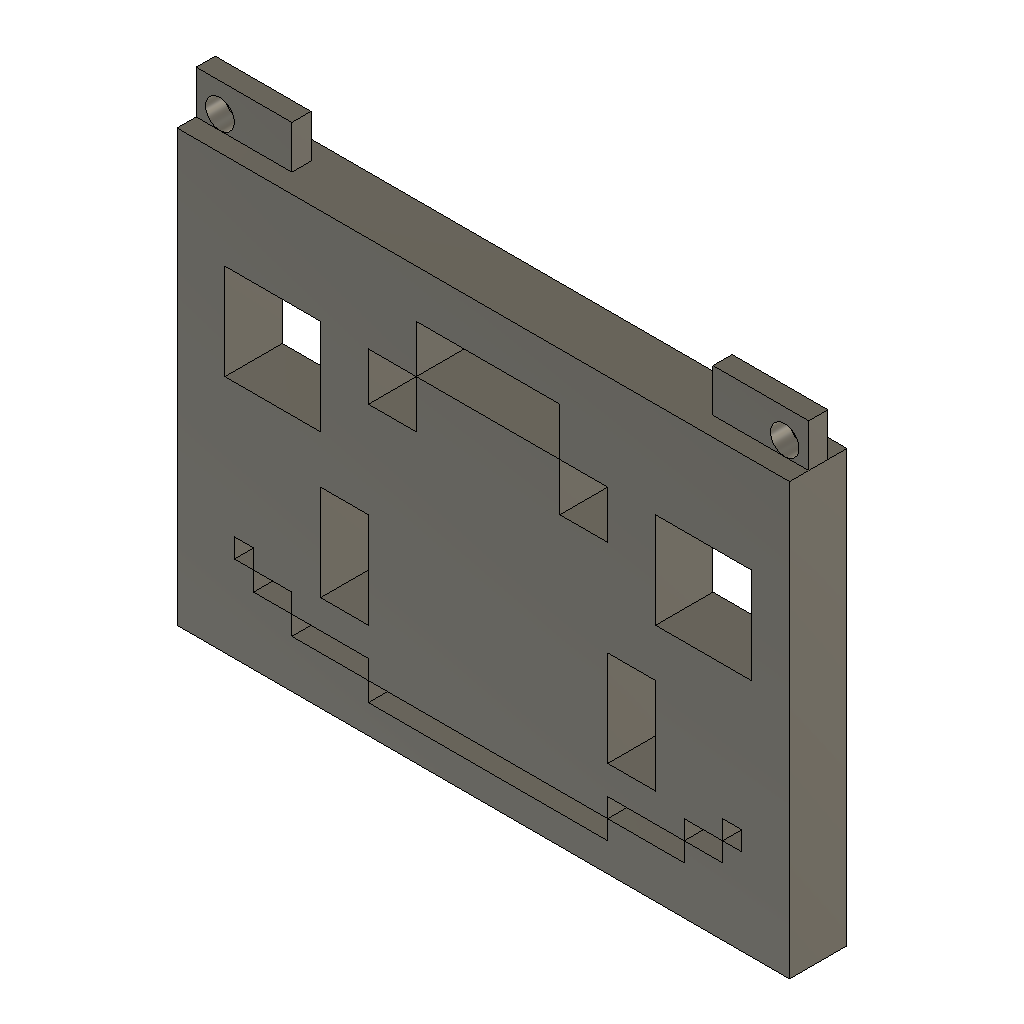
小车设计 (Autodesk Fusion 360 archive; units mm, degrees)
design "挡板1"
part number: 2026-10-10-23-06-53-634
Autodesk Fusion 360 part; units mm, degrees
sketch "草图1" plane through (0, 0, 0) normal (0, 0, 1) x (1, 0, 0)
  line L0 (0, 0) -> (64, 0)
  line L1 (64, 0) -> (64, -6)
  line L2 (64, -6) -> (0, -6)
  line L3 (0, -6) -> (0, 0)
  line L4 (0, -2) -> (10, -2)
  line L5 (0, -4) -> (10, -4)
  line L6 (10, -2) -> (10, -4)
  line L7 (0, -2) -> (0, -4)
  line L8 (64, -2) -> (54, -2)
  line L9 (54, -2) -> (54, -4)
  line L10 (54, -4) -> (64, -4)
  line L11 (64, -2) -> (64, -4)
  dimension "d1" = 64
  dimension "d2" = 6
  constraint horizontal L0
  constraint vertical L1
  constraint horizontal L2
  constraint vertical L3
  constraint coincident L0.start L3.end
  constraint coincident L3 L4.start
  constraint perpendicular L3 L4
  constraint coincident L3 L5.start
  constraint perpendicular L3 L5
  constraint perpendicular L5 L6
  constraint coincident L1 L8.start
  constraint perpendicular L1 L8
  constraint perpendicular L8 L9
  constraint coincident L1 L10.end
  constraint perpendicular L1 L10
  measures "d1" distance of L0.start L0.end
  measures "d2" distance of L0.start L2.end
extrude "拉伸1" add sketch "草图1" along normal blind 4.5 contours L3 L4 L5 L6 L7 | L1 L8 L9 L10 L11 makes body 1 at (3.3333, -2, 1.5) makes body 2 at (60.6667, -2, 1.5)
sketch "草图2" plane through (0, 0, 0) normal (0, 0, 1) x (1, 0, 0)
  line L0 (0, 0) -> (64, 0)
  line L1 (64, 0) -> (64, -6)
  line L2 (64, -6) -> (0, -6)
  line L3 (0, -6) -> (0, 0)
  constraint horizontal L0
  constraint vertical L1
  constraint horizontal L2
  constraint vertical L3
  constraint coincident L0.start L3.end
extrude "拉伸2" add sketch "草图2" against normal blind 45 bodies 1 2
sketch "草图3" plane through (0, 0, 0) normal (0, 1, 0) x (1, 0, 0)
sketch "草图6" plane through (0, -4, 0) normal (0, -1, 0) x (1, 0, 0)
  line L0 (54, 0) -> (64, 0)
  line L1 (64, 0) -> (64, 4.5)
  line L2 (64, 4.5) -> (54, 4.5)
  line L3 (54, 4.5) -> (54, 0)
  line L4 (10, 4.5) -> (0, 4.5)
  line L5 (0, 0) -> (10, 0)
  line L6 (0.9797, 4.5) -> (0.9797, 0)
  circle A0 centre (2.4797, 1.5) radius 1.5
  line L7 (63, 0) -> (63, 4.5)
  circle A1 centre (61.5, 1.5) radius 1.5
  dimension "d15" = 1.5
  dimension "d16" = 1.5
  constraint coincident L4 L6.start
  constraint coincident L5 L6.end
  constraint perpendicular L5 L6
  constraint tangent L6 A0
  constraint tangent L5 A0
  constraint coincident L0 L7.start
  constraint coincident L2 L7.end
  constraint perpendicular L2 L7
  constraint tangent L7 A1
  constraint tangent L0 A1
  measures "d15" radius of A0
  measures "d16" radius of A1
extrude "拉伸5" cut sketch "草图6" against normal blind 9 contours A1 | A0 bodies 1
sketch "草图7" plane through (0, -6, 0) normal (0, -1, 0) x (1, 0, 0)
  line L0 (64, 0) -> (0, 0)
  line L1 (0, 0) -> (0, -45)
  line L2 (0, -45) -> (64, -45)
  line L3 (64, -45) -> (64, 0)
  line L4 (50, -35) -> (45, -35)
  line L5 (45, -35) -> (45, -25)
  line L6 (45, -25) -> (50, -25)
  line L7 (50, -25) -> (50, -35)
  line L8 (20, -35) -> (15, -35)
  line L9 (15, -35) -> (15, -25)
  line L10 (15, -25) -> (20, -25)
  line L11 (20, -25) -> (20, -35)
  line L12 (40, -10) -> (25, -10)
  line L13 (25, -10) -> (25, -5)
  line L14 (25, -5) -> (40, -5)
  line L15 (40, -5) -> (40, -10)
  line L16 (20, -10) -> (25, -10)
  line L17 (25, -10) -> (25, -15)
  line L18 (25, -15) -> (20, -15)
  line L19 (20, -15) -> (20, -10)
  line L20 (45, -10) -> (40, -10)
  line L21 (40, -10) -> (40, -15)
  line L22 (40, -15) -> (45, -15)
  line L23 (45, -15) -> (45, -10)
  line L24 (5, -20) -> (15, -20)
  line L25 (15, -20) -> (15, -10)
  line L26 (15, -10) -> (5, -10)
  line L27 (5, -10) -> (5, -20)
  line L28 (60, -20) -> (50, -20)
  line L29 (50, -20) -> (50, -10)
  line L30 (50, -10) -> (60, -10)
  line L31 (60, -10) -> (60, -20)
  point P0 (45, -25)
  point P1 (50, -25)
  point P2 (50, -35)
  point P3 (45, -35)
  point P4 (20, -35)
  point P5 (15, -35)
  point P6 (15, -25)
  point P7 (20, -25)
  point P8 (40, -10)
  point P9 (25, -10)
  point P10 (40, -5)
  point P11 (25, -5)
  point P12 (45, -10)
  point P13 (20, -10)
  point P14 (60, -20)
  point P15 (5, -20)
  constraint horizontal L4
  constraint vertical L5
  constraint horizontal L6
  constraint vertical L7
  constraint coincident P0 L5.end
  constraint coincident P2 L4.start
  constraint horizontal L8
  constraint vertical L9
  constraint horizontal L10
  constraint vertical L11
  constraint coincident P6 L9.end
  constraint coincident P4 L8.start
  constraint horizontal L12
  constraint vertical L13
  constraint horizontal L14
  constraint vertical L15
  constraint coincident P11 L13.end
  constraint coincident P8 L12.start
  constraint horizontal L16
  constraint vertical L17
  constraint horizontal L18
  constraint vertical L19
  constraint coincident P13 L16.start
  constraint horizontal L20
  constraint vertical L21
  constraint horizontal L22
  constraint vertical L23
  constraint coincident P12 L20.start
  constraint horizontal L24
  constraint vertical L25
  constraint horizontal L26
  constraint vertical L27
  constraint coincident P15 L24.start
  constraint horizontal L28
  constraint vertical L29
  constraint horizontal L30
  constraint vertical L31
  constraint coincident P14 L28.start
extrude "拉伸6" cut sketch "草图7" against normal blind 21 contours L4 L5 L6 L7 | L8 L9 L10 L11 | L16 L17 L18 L19 | L12 L13 L14 L15 | L20 L21 L22 L23 bodies 1
sketch "草图8" plane through (0, 0, 0) normal (0, 1, 0) x (-1, 0, 0)
  line L0 (-45, -25) -> (-45, -35)
  line L1 (-45, -35) -> (-50, -35)
  line L2 (-50, -35) -> (-50, -25)
  line L3 (-50, -25) -> (-45, -25)
  line L4 (-15, -25) -> (-15, -35)
  line L5 (-15, -35) -> (-20, -35)
  line L6 (-20, -35) -> (-20, -25)
  line L7 (-20, -25) -> (-15, -25)
  line L8 (-25, -15) -> (-25, -10)
  line L9 (-25, -10) -> (-40, -10)
  line L10 (-40, -10) -> (-40, -15)
  line L11 (-40, -15) -> (-45, -15)
  line L12 (-45, -15) -> (-45, -10)
  line L13 (-45, -10) -> (-40, -10)
  line L14 (-40, -10) -> (-40, -5)
  line L15 (-40, -5) -> (-25, -5)
  line L16 (-25, -5) -> (-25, -10)
  line L17 (-25, -10) -> (-20, -10)
  line L18 (-20, -10) -> (-20, -15)
  line L19 (-20, -15) -> (-25, -15)
  line L20 (0, 0) -> (-64, 0)
  line L21 (-64, 0) -> (-64, -45)
  line L22 (-64, -45) -> (0, -45)
  line L23 (0, -45) -> (0, 0)
  line L24 (-15, -10) -> (-5, -10)
  line L25 (-5, -10) -> (-5, -20)
  line L26 (-5, -20) -> (-15, -20)
  line L27 (-15, -20) -> (-15, -10)
  line L28 (-50, -10) -> (-60, -10)
  line L29 (-60, -10) -> (-60, -20)
  line L30 (-60, -20) -> (-50, -20)
  line L31 (-50, -20) -> (-50, -10)
  constraint horizontal L24
  constraint vertical L25
  constraint horizontal L26
  constraint vertical L27
  constraint horizontal L28
  constraint vertical L29
  constraint horizontal L30
  constraint vertical L31
extrude "拉伸7" cut sketch "草图8" against normal blind 17 contours L24 L25 L26 L27 | L28 L29 L30 L31 bodies 1
sketch "草图9" plane through (0, -6, 0) normal (0, -1, 0) x (1, 0, 0)
  line L0 (5, -20) -> (5, -10)
  line L1 (5, -10) -> (15, -10)
  line L2 (15, -10) -> (15, -20)
  line L3 (15, -20) -> (5, -20)
  line L4 (50, -10) -> (60, -10)
  line L5 (60, -10) -> (60, -20)
  line L6 (60, -20) -> (50, -20)
  line L7 (50, -20) -> (50, -10)
  line L8 (45, -35) -> (45, -25)
  line L9 (45, -25) -> (50, -25)
  line L10 (50, -25) -> (50, -35)
  line L11 (50, -35) -> (45, -35)
  line L12 (15, -35) -> (15, -25)
  line L13 (15, -25) -> (20, -25)
  line L14 (20, -25) -> (20, -35)
  line L15 (20, -35) -> (15, -35)
  line L16 (25, -10) -> (25, -15)
  line L17 (25, -15) -> (20, -15)
  line L18 (20, -15) -> (20, -10)
  line L19 (20, -10) -> (25, -10)
  line L20 (25, -10) -> (25, -5)
  line L21 (25, -5) -> (40, -5)
  line L22 (40, -5) -> (40, -10)
  line L23 (40, -10) -> (45, -10)
  line L24 (45, -10) -> (45, -15)
  line L25 (45, -15) -> (40, -15)
  line L26 (40, -15) -> (40, -10)
  line L27 (40, -10) -> (25, -10)
  line L28 (64, 0) -> (0, 0)
  line L29 (0, 0) -> (0, -45)
  line L30 (0, -45) -> (64, -45)
  line L31 (64, -45) -> (64, 0)
  line L32 (45, -42) -> (20, -42)
  line L33 (20, -42) -> (20, -40)
  line L34 (20, -40) -> (45, -40)
  line L35 (45, -40) -> (45, -42)
  line L36 (20, -40) -> (12, -40)
  line L37 (12, -40) -> (12, -38)
  line L38 (12, -38) -> (20, -38)
  line L39 (20, -38) -> (20, -40)
  line L40 (12, -38) -> (8, -38)
  line L41 (8, -38) -> (8, -36)
  line L42 (8, -36) -> (12, -36)
  line L43 (12, -36) -> (12, -38)
  line L44 (8, -36) -> (6, -36)
  line L45 (6, -36) -> (6, -34)
  line L46 (6, -34) -> (8, -34)
  line L47 (8, -34) -> (8, -36)
  line L48 (6, -34) -> (4, -34)
  line L49 (4, -34) -> (4, -32)
  line L50 (4, -32) -> (6, -32)
  line L51 (6, -32) -> (6, -34)
  line L52 (4, -32) -> (2, -32)
  line L53 (2, -32) -> (2, -30)
  line L54 (2, -30) -> (4, -30)
  line L55 (4, -30) -> (4, -32)
  line L56 (45, -40) -> (53, -40)
  line L57 (53, -40) -> (53, -38)
  line L58 (53, -38) -> (45, -38)
  line L59 (45, -38) -> (45, -40)
  line L60 (53, -38) -> (57, -38)
  line L61 (57, -38) -> (57, -36)
  line L62 (57, -36) -> (53, -36)
  line L63 (53, -36) -> (53, -38)
  line L64 (57, -36) -> (59, -36)
  line L65 (59, -36) -> (59, -34)
  line L66 (59, -34) -> (57, -34)
  line L67 (57, -34) -> (57, -36)
  line L68 (59, -34) -> (61, -34)
  line L69 (61, -34) -> (61, -32)
  line L70 (61, -32) -> (59, -32)
  line L71 (59, -32) -> (59, -34)
  line L72 (61, -32) -> (63, -32)
  line L73 (63, -32) -> (63, -30)
  line L74 (63, -30) -> (61, -30)
  line L75 (61, -30) -> (61, -32)
  point P0 (45, -42)
  point P1 (20, -42)
  point P2 (16, -39)
  point P3 (18, -40)
  point P4 (12, -38)
  point P5 (8, -36)
  point P6 (6, -34)
  point P7 (4, -32)
  point P8 (4, -30)
  point P9 (2, -30)
  point P10 (45, -40)
  point P11 (20, -40)
  point P12 (53, -38)
  point P13 (57, -36)
  point P14 (59, -34)
  point P15 (61, -32)
  point P16 (63, -30)
  constraint horizontal L32
  constraint vertical L33
  constraint horizontal L34
  constraint vertical L35
  constraint coincident P11 L33.end
  constraint coincident P0 L32.start
  constraint horizontal L36
  constraint vertical L37
  constraint horizontal L38
  constraint vertical L39
  constraint coincident P4 L37.end
  constraint horizontal L40
  constraint vertical L41
  constraint horizontal L42
  constraint vertical L43
  constraint coincident P5 L41.end
  constraint horizontal L44
  constraint vertical L45
  constraint horizontal L46
  constraint vertical L47
  constraint coincident P6 L45.end
  constraint horizontal L48
  constraint vertical L49
  constraint horizontal L50
  constraint vertical L51
  constraint coincident P7 L49.end
  constraint horizontal L52
  constraint vertical L53
  constraint horizontal L54
  constraint vertical L55
  constraint coincident P9 L53.end
  constraint horizontal L56
  constraint vertical L57
  constraint horizontal L58
  constraint vertical L59
  constraint coincident P12 L57.end
  constraint coincident P10 L34.end
  constraint horizontal L60
  constraint vertical L61
  constraint horizontal L62
  constraint vertical L63
  constraint coincident P13 L61.end
  constraint horizontal L64
  constraint vertical L65
  constraint horizontal L66
  constraint vertical L67
  constraint coincident P14 L65.end
  constraint horizontal L68
  constraint vertical L69
  constraint horizontal L70
  constraint vertical L71
  constraint coincident P15 L69.end
  constraint horizontal L72
  constraint vertical L73
  constraint horizontal L74
  constraint vertical L75
  constraint coincident P16 L73.end
extrude "拉伸8" cut sketch "草图9" against normal blind 36 contours L44 L45 L46 L47 | L40 L41 L42 L43 | L36 L37 L38 L39 | L64 L65 L66 L67 | L60 L61 L62 L63 | L56 L57 L58 L59 | L32 L33 L34 L35 bodies 1

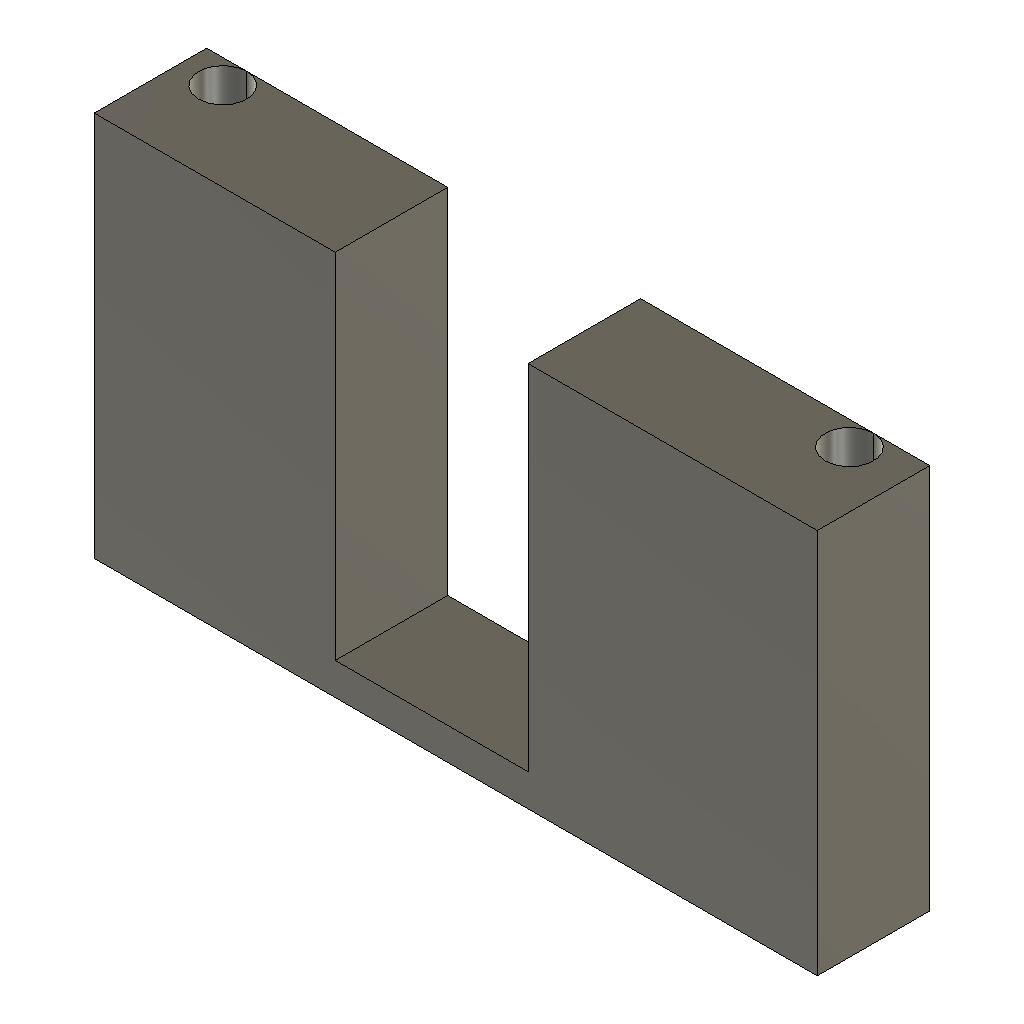
design "舵机固定"
part number: 2026-10-10-18-02-42-564
Autodesk Fusion 360 part; units mm, degrees
sketch "草图3" plane through (0, 0, 0) normal (0, 0, 1) x (1, 0, 0)
  line L0 (0, 0) -> (45, 0)
  line L1 (45, 0) -> (45, -7)
  line L2 (45, -7) -> (0, -7)
  line L3 (0, -7) -> (0, 0)
  point P0 (42, 0)
  point P1 (39, 0)
  point P2 (27, 0)
  point P3 (15, 0)
  point P4 (4.7006, 0)
  point P5 (2, 0)
  dimension "d3" = 45
  constraint horizontal L0
  constraint vertical L1
  constraint horizontal L2
  constraint vertical L3
  constraint coincident L0.start L3.end
  constraint coincident L0 P0
  constraint coincident L0 P1
  constraint coincident L0 P2
  constraint coincident L0 P3
  constraint coincident L0 P4
  constraint coincident L0 P5
  measures "d3" distance of L0.start L0.end
extrude "拉伸1" add sketch "草图3" along normal blind 24
sketch "草图4" plane through (0, 0, 24) normal (0, 0, 1) x (-1, 0, 0)
  line L0 (0, 7) -> (-45, 7)
  line L1 (-45, 7) -> (-45, 0)
  line L2 (-45, 0) -> (0, 0)
  line L3 (0, 0) -> (0, 7)
  line L4 (-15, 0) -> (-27, 0)
  line L5 (-27, 0) -> (-27, 7)
  line L6 (-27, 7) -> (-15, 7)
  line L7 (-15, 7) -> (-15, 0)
  circle A0 centre (-40.5, 1.5) radius 1.5
  circle A1 centre (-2.5001, 1.5001) radius 1.5001
  point P0 (-42, 0)
  point P1 (-39, 0)
  point P2 (-27, 0)
  point P3 (-15, 0)
  point P4 (-4, 0)
  point P5 (-15, 0)
  point P6 (-15, 0)
  dimension "d7" = 3
  constraint coincident L2 P0
  constraint coincident L2 P1
  constraint coincident L2 P2
  constraint coincident L2 P6
  constraint coincident L2 P4
  constraint coincident P6 P5
  constraint horizontal L4
  constraint vertical L5
  constraint horizontal L6
  constraint vertical L7
  constraint coincident L0 L5.end
  measures "d7" diameter of A0
extrude "拉伸2" cut sketch "草图4" against normal blind 22 contours L0 L2 L4 L5 L6 L7
sketch "草图5" plane through (0, 0, 24) normal (0, 0, 1) x (-1, 0, 0)
  line L0 (-15, 7) -> (-15, 0)
  line L1 (-15, 0) -> (0, 0)
  line L2 (0, 0) -> (0, 7)
  line L3 (0, 7) -> (-15, 7)
  line L4 (-1, 0) -> (-4, 0)
  line L5 (-1, 0) -> (-1, 5)
  circle A0 centre (-2.5, 1.5) radius 1.5
  line L6 (-45, 0) -> (-27, 0)
  line L7 (0, 0) -> (-45, 0)
  line L8 (-43, 0) -> (-40, 0)
  line L9 (-40, 4) -> (-40, 0)
  circle A1 centre (-41.5, 1.5) radius 1.5
  dimension "d10" = 1.5
  dimension "d11" = 1.5
  constraint coincident L1 L4.start
  constraint coincident L1 L4.end
  constraint perpendicular L4 L5
  constraint tangent L4 A0
  constraint tangent L5 A0
  constraint coincident L6 L8.start
  constraint coincident L6 L8.end
  constraint perpendicular L6 L9
  constraint tangent L8 A1
  constraint tangent L9 A1
  measures "d10" radius of A0
  measures "d11" radius of A1
extrude "拉伸3" cut sketch "草图5" against normal blind 37 contours A0 | A1

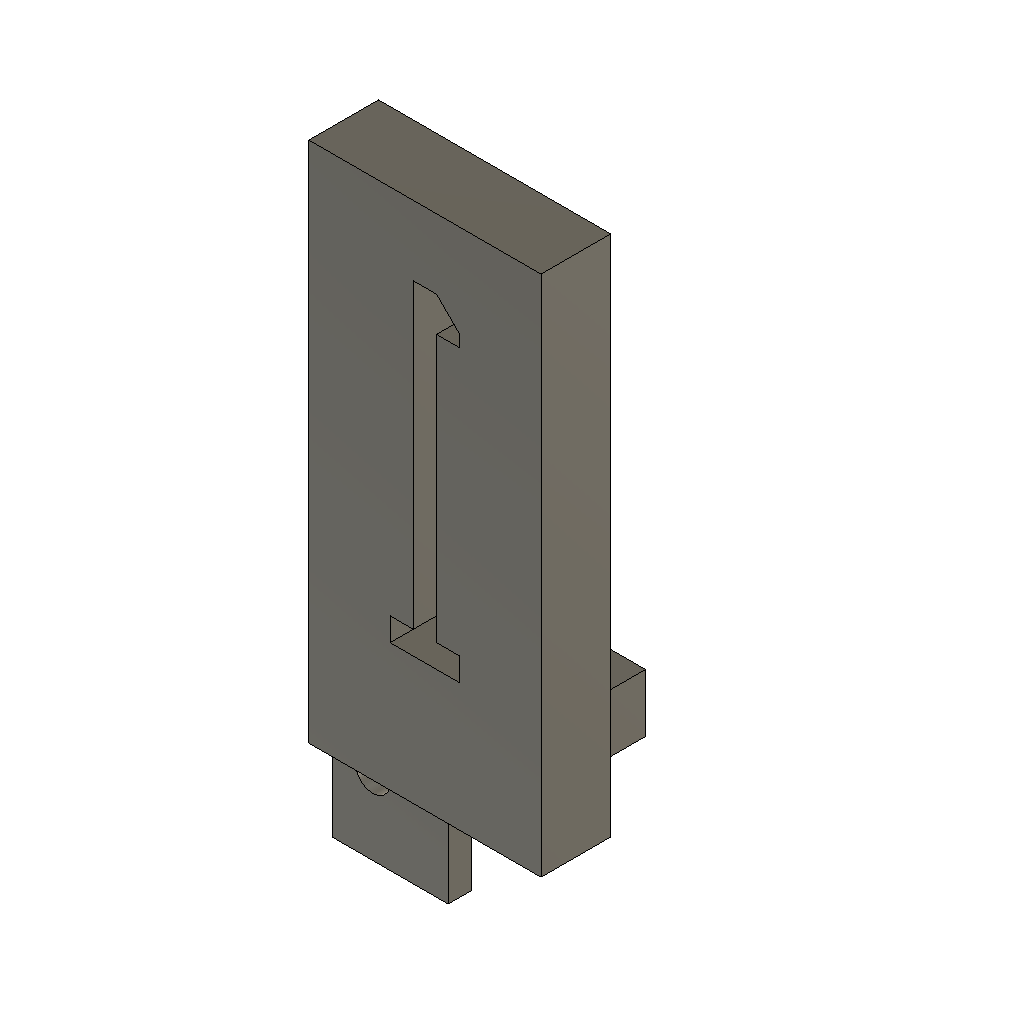
design "挡板2"
part number: 2026-10-11-00-40-43-572
Autodesk Fusion 360 part; units mm, degrees
sketch "草图1" plane through (0, 0, 0) normal (0, 0, 1) x (1, 0, 0)
  line L0 (0, 0) -> (20, 0)
  line L1 (20, 0) -> (20, -6)
  line L2 (20, -6) -> (0, -6)
  line L3 (0, -6) -> (0, 0)
  dimension "d1" = 20
  dimension "d2" = 6
  constraint horizontal L0
  constraint vertical L1
  constraint horizontal L2
  constraint vertical L3
  constraint coincident L0.start L3.end
  measures "d1" distance of L0.start L0.end
  measures "d2" distance of L0.start L2.end
extrude "拉伸1" add sketch "草图1" along normal blind 45
sketch "草图2" plane through (0, 0, 0) normal (0, 0, -1) x (1, 0, 0)
  line L0 (20, 6) -> (0, 6)
  line L1 (0, 6) -> (0, 0)
  line L2 (0, 0) -> (20, 0)
  line L3 (20, 0) -> (20, 6)
  line L4 (0, 4) -> (10, 4)
  line L5 (10, 4) -> (10, 2)
  line L6 (10, 2) -> (0, 2)
  line L7 (0, 4) -> (0, 2)
  constraint coincident L1 L4.start
  constraint perpendicular L1 L4
  constraint perpendicular L4 L5
  constraint coincident L1 L6.end
  constraint perpendicular L1 L6
extrude "拉伸2" add sketch "草图2" along normal blind 8 contours L1 L4 L5 L6 L7
sketch "草图3" plane through (0, -2, 0) normal (0, 1, 0) x (-1, 0, 0)
  line L0 (0, 0) -> (-10, 0)
  line L1 (-10, 0) -> (-10, -8)
  line L2 (-10, -8) -> (0, -8)
  line L3 (0, -8) -> (0, 0)
  line L4 (-2, -8) -> (-2, 0)
  circle A0 centre (-3.5, -1.5) radius 1.5
  dimension "d7" = 1.5
  constraint coincident L2 L4.start
  constraint coincident L0 L4.end
  constraint tangent L4 A0
  constraint tangent L0 A0
  measures "d7" radius of A0
extrude "拉伸3" cut sketch "草图3" against normal blind 20 contours A0
sketch "草图4" plane through (0, 0, 0) normal (0, 1, 0) x (-1, 0, 0)
  line L0 (-20, 0) -> (0, 0)
  line L1 (0, 0) -> (0, 45)
  line L2 (0, 45) -> (-20, 45)
  line L3 (-20, 45) -> (-20, 0)
  line L4 (-8, 0) -> (-8, 5)
  line L5 (-8, 5) -> (-14, 5)
  line L6 (-14, 5) -> (-14, 0)
  constraint coincident L0 L4.start
  constraint perpendicular L0 L4
  constraint perpendicular L4 L5
  constraint coincident L0 L6.end
  constraint perpendicular L0 L6
extrude "拉伸4" add sketch "草图4" along normal blind 9 contours L0 L4 L5 L6
sketch "草图5" plane through (0, 0, 5) normal (0, 0, 1) x (-1, 0, 0)
  line L0 (-8, 0) -> (-14, 0)
  line L1 (-14, 0) -> (-14, -9)
  line L2 (-14, -9) -> (-8, -9)
  line L3 (-8, -9) -> (-8, 0)
  line L4 (-11, 0) -> (-9.5, 0)
  line L5 (-9.5, 0) -> (-9.5, -7)
  line L6 (-9.5, -7) -> (-11, -7)
  line L7 (-11, -7) -> (-11, 0)
  line L8 (-11, 0) -> (-12.5, 0)
  line L9 (-12.5, 0) -> (-12.5, -7)
  line L10 (-12.5, -7) -> (-11, -7)
  line L11 (-11, -7) -> (-11, 0)
  dimension "d12" = 1.5
  dimension "d13" = 7
  dimension "d14" = 7
  constraint horizontal L4
  constraint vertical L5
  constraint horizontal L6
  constraint vertical L7
  constraint midpoint L0 L4.start
  constraint horizontal L8
  constraint vertical L9
  constraint horizontal L10
  constraint vertical L11
  measures "d12" distance of L4.start L4.end
  measures "d13" distance of L4.start L6.end
  measures "d14" distance of L4.start L6.end
extrude "拉伸5" cut sketch "草图5" against normal blind 17 contours L0 L4 L5 L6 L7 L11 | L0 L7 L8 L9 L10 L11
sketch "草图6" plane through (0, 0, 0) normal (0, 1, 0) x (-1, 0, 0)
  line L0 (-8, 5) -> (-8, 0)
  line L1 (-8, 0) -> (0, 0)
  line L2 (0, 0) -> (0, 45)
  line L3 (0, 45) -> (-20, 45)
  line L4 (-20, 45) -> (-20, 0)
  line L5 (-20, 0) -> (-14, 0)
  line L6 (-14, 0) -> (-14, 5)
  line L7 (-14, 5) -> (-12.5, 5)
  line L8 (-12.5, 5) -> (-12.5, 0)
  line L9 (-12.5, 0) -> (-9.5, 0)
  line L10 (-9.5, 0) -> (-9.5, 5)
  line L11 (-9.5, 5) -> (-8, 5)
  line L12 (-11, 13) -> (-9, 13)
  line L13 (-9, 13) -> (-9, 36)
  line L14 (-9, 36) -> (-11, 36)
  line L15 (-11, 36) -> (-11, 13)
  line L16 (-13, 36) -> (-9, 36)
  line L17 (-9, 36) -> (-9, 37)
  line L18 (-9, 37) -> (-13, 37)
  line L19 (-13, 37) -> (-13, 36)
  line L20 (-11, 39) -> (-9, 39)
  line L21 (-9, 39) -> (-9, 37)
  line L22 (-9, 37) -> (-11, 37)
  line L23 (-11, 37) -> (-11, 39)
  line L24 (-11, 39) -> (-13, 37)
  line L25 (-13, 13) -> (-7, 13)
  line L26 (-7, 13) -> (-7, 11)
  line L27 (-7, 11) -> (-13, 11)
  line L28 (-13, 11) -> (-13, 13)
  constraint horizontal L12
  constraint vertical L13
  constraint horizontal L14
  constraint vertical L15
  constraint horizontal L16
  constraint vertical L17
  constraint horizontal L18
  constraint vertical L19
  constraint horizontal L20
  constraint vertical L21
  constraint horizontal L22
  constraint vertical L23
  constraint horizontal L25
  constraint vertical L26
  constraint horizontal L27
  constraint vertical L28
extrude "拉伸6" cut sketch "草图6" against normal blind 10 contours L12 L13 L14 L15 L16 L25 | L12 L25 L26 L27 L28 | L14 L16 L17 L18 L19 L22 | L18 L20 L21 L22 L23 | L18 L23 L24

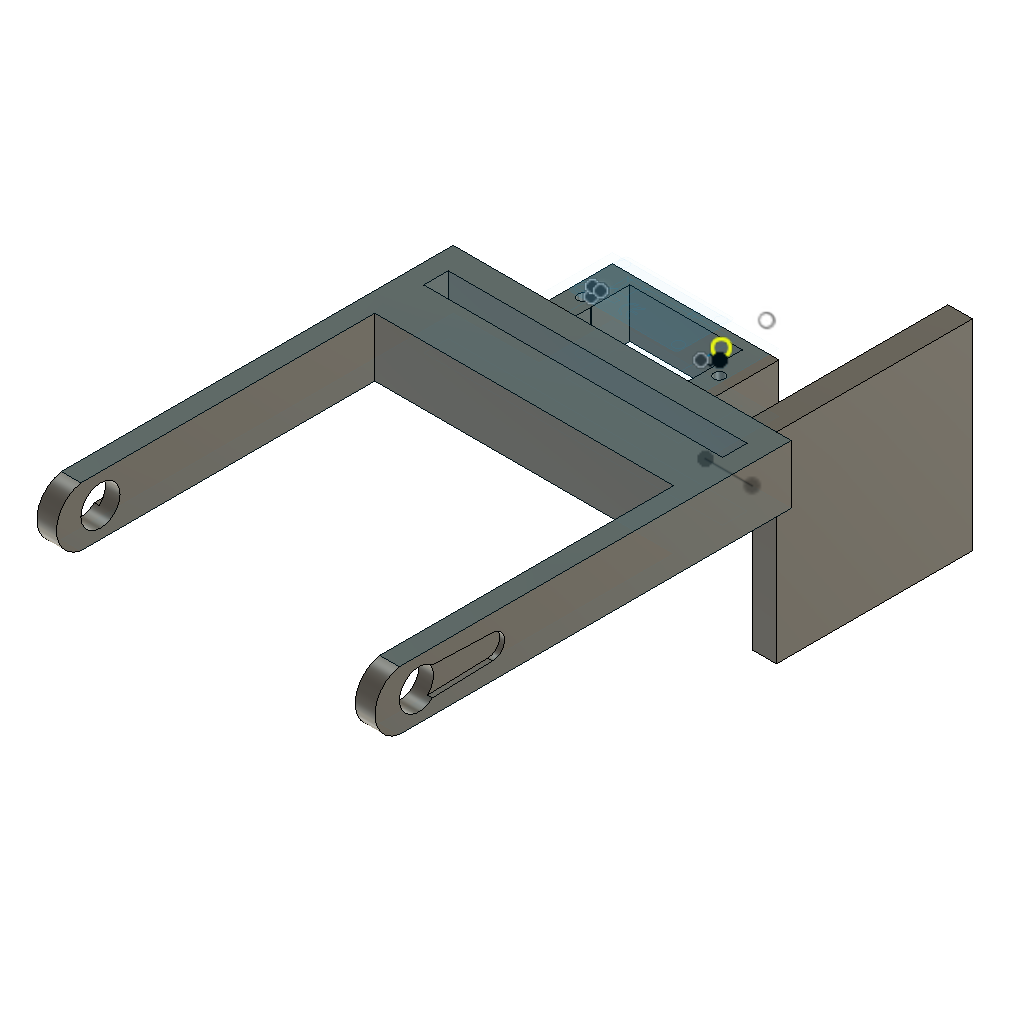
design "爪机（改）"
part number: 2026-10-15-23-02-40-498
Autodesk Fusion 360 part; units mm, degrees
sketch "草图1" plane through (0, 0, 0) normal (0, 0, 1) x (1, 0, 0)
  line L0 (0, 0) -> (69, 0)
  line L1 (69, 0) -> (69, -80)
  line L2 (0, -80) -> (0, 0)
  line L3 (0, -80) -> (4, -80)
  line L4 (69, -80) -> (65, -80)
  line L5 (4, -80) -> (4, -20)
  line L6 (65, -80) -> (65, -20)
  line L7 (4, -20) -> (65, -20)
  line L8 (4, -20) -> (4, -10)
  line L9 (4, -10) -> (4, -5)
  line L10 (4, -10) -> (65, -10)
  line L11 (4, -5) -> (65, -5)
  line L12 (65, -5) -> (65, -10)
  line L13 (65, -10) -> (65, -20)
  point P0 (4, -80)
  point P1 (65, -80)
  dimension "d1" = 69
  dimension "d2" = 80
  dimension "d3" = 4
  dimension "d4" = 4
  dimension "d5" = 60
  dimension "d6" = 60
  dimension "d7" = 10
  dimension "d8" = 5
  constraint horizontal L0
  constraint vertical L1
  constraint vertical L2
  constraint coincident L0.start L2.end
  constraint perpendicular L2 L3
  constraint perpendicular L1 L4
  constraint perpendicular L3 L5
  constraint perpendicular L7 L8
  constraint parallel L8 L9
  constraint perpendicular L9 L10
  constraint perpendicular L9 L11
  constraint perpendicular L10 L12
  constraint perpendicular L7 L13
  constraint coincident P0 L3.end
  constraint coincident P1 L4.end
  measures "d1" distance of L0.start L0.end
  measures "d2" distance of L0.start L2.start
  measures "d3" distance of L2.start P0
  measures "d4" distance of L1.end P1
  measures "d5" distance of P0 L5.end
  measures "d6" distance of P1 L6.end
  measures "d7" distance of L5.end L8.end
  measures "d8" distance of L8.end L9.end
extrude "拉伸1" add sketch "草图1" along normal blind 12 contours L0 L1 L2 L3 L4 L5 L6 L8 L9 L11 L12 L13 | L7 L8 L10 L13 makes body 1
sketch "草图2" plane through (0, 0, 0) normal (-1, 0, 0) x (0, -1, 0)
  line L0 (0, 0) -> (80, 0)
  line L1 (80, 0) -> (80, 12)
  line L2 (80, 12) -> (0, 12)
  line L3 (0, 12) -> (0, 0)
  arc A0 (80, 0) -> (80, 12) centre (78.9, 6) ccw
  arc A1 (80, 0) -> (80, 12) centre (78.9, 6) ccw
  constraint coincident L0.end L1.start
  constraint coincident L1.end L2.start
extrude "拉伸2" add sketch "草图2" against normal blind 4 contours L1 A0 A1 bodies 1
sketch "草图3" plane through (69, 0, 0) normal (1, 0, 0) x (0, 1, 0)
  line L0 (-80, 0) -> (0, 0)
  line L1 (0, 0) -> (0, 12)
  line L2 (0, 12) -> (-80, 12)
  line L3 (-80, 12) -> (-80, 0)
  arc A0 (-80, 12) -> (-80, 0) centre (-78.9, 6) ccw
  constraint coincident L2.end L3.start
  constraint coincident L0.start L3.end
extrude "拉伸3" add sketch "草图3" against normal blind 4 contours L3 A0 bodies 1
sketch "草图4" plane through (69, 0, 0) normal (1, 0, 0) x (0, 1, 0)
  line L0 (-80, 0) -> (0, 0)
  line L1 (0, 0) -> (0, 12)
  line L2 (0, 12) -> (-80, 12)
  arc A0 (-80, 12) -> (-80, 0) centre (-78.9, 6) ccw
  line L3 (-80, 12) -> (-80, 0) construction
  line L4 (-80, 6) -> (-76, 6) construction
  line L5 (-76, 6) -> (-73.354, 6) construction
  line L6 (-76, 6) -> (-61, 6) construction
  circle A1 centre (-76, 6) radius 4
  circle A2 centre (-61, 6) radius 2.5
  line L7 (-61, 8.5) -> (-73.354, 8.9998)
  line L8 (-61, 3.5) -> (-73.354, 3.0002)
  dimension "d15" = 4
  dimension "d16" = 2.646
  dimension "d17" = 15
  dimension "d18" = 8
  dimension "d19" = 5
  constraint coincident L2.end A0.start
  constraint coincident L0.start A0.end
  constraint midpoint L3 L4.start
  constraint perpendicular L3 L4
  constraint perpendicular L3 L5
  constraint perpendicular L3 L6
  constraint coincident L4.end L5.start
  constraint coincident L6.end A2.centre
  constraint coincident A2 L7.start
  constraint coincident A1 L7.end
  constraint coincident A2 L8.start
  constraint coincident A1 L8.end
  measures "d15" distance of L4.start L4.end
  measures "d16" distance of L4.end L5.end
  measures "d17" distance of L4.end L6.end
  measures "d18" diameter of A1
  measures "d19" diameter of A2
extrude "拉伸4" cut sketch "草图4" against normal blind 107 contours A1 bodies 1
sketch "草图5" plane through (69, 0, 0) normal (1, 0, 0) x (0, 1, 0)
  circle A0 centre (-76, 6) radius 4
  line L0 (-80, 0) -> (0, 0)
  line L1 (0, 0) -> (0, 12)
  line L2 (0, 12) -> (-80, 12)
  arc A1 (-80, 12) -> (-80, 0) centre (-78.9, 6) ccw
  line L3 (-76, 6) -> (-61, 6) construction
  line L4 (-76, 6) -> (-73.354, 6) construction
  circle A2 centre (-61, 6) radius 2.5
  line L5 (-61, 8.5) -> (-73.3002, 8.9515)
  line L6 (-61, 3.5) -> (-73.2409, 3.1039)
  dimension "d22" = 15
  dimension "d23" = 2.646
  dimension "d24" = 5
  constraint coincident A0.centre L3.start
  constraint horizontal L3
  constraint parallel L3 L4
  constraint coincident L3.end A2.centre
  constraint coincident A2 L5.start
  constraint coincident A0 L5.end
  constraint coincident A2 L6.start
  constraint coincident A0 L6.end
  measures "d22" distance of A0.centre L3.end
  measures "d23" distance of A0.centre L4.end
  measures "d24" diameter of A2
extrude "拉伸5" cut sketch "草图5" against normal blind 1 contours A0 A2 L5 L6 | A2 bodies 1
sketch "草图6" plane through (0, 0, 0) normal (-1, 0, 0) x (0, -1, 0)
  circle A0 centre (76, 6) radius 4
  line L0 (0, 0) -> (80, 0)
  arc A1 (80, 0) -> (80, 12) centre (78.9, 6) ccw
  line L1 (80, 12) -> (0, 12)
  line L2 (0, 12) -> (0, 0)
  line L3 (76, 6) -> (61, 6) construction
  line L4 (76, 6) -> (73.354, 6) construction
  circle A2 centre (61, 6) radius 2.5
  line L5 (61, 8.5) -> (73.3002, 8.9515)
  line L6 (61, 3.5) -> (73.2409, 3.1039)
  point P0 (61, 8.5)
  point P1 (73.3002, 8.9515)
  point P2 (61, 3.5)
  point P3 (73.2409, 3.1039)
  dimension "d27" = 15
  dimension "d28" = 2.646
  dimension "d29" = 5
  constraint coincident A0.centre L3.start
  constraint horizontal L3
  constraint parallel L3 L4
  constraint coincident L3.end A2.centre
  constraint coincident P0 L5.start
  constraint coincident P1 L5.end
  constraint coincident P2 L6.start
  constraint coincident P3 L6.end
  measures "d27" distance of A0.centre L3.end
  measures "d28" distance of A0.centre L4.end
  measures "d29" diameter of A2
extrude "拉伸6" cut sketch "草图6" against normal blind 1 contours A0 A2 L5 L6 | A2 bodies 1
sketch "草图7" plane through (0, 0, 12) normal (0, 0, 1) x (-1, 0, 0)
  line L0 (-65, 10) -> (-4, 10)
  line L1 (-4, 10) -> (-4, 5)
  line L2 (-4, 5) -> (-65, 5)
  line L3 (-65, 5) -> (-65, 10)
  line L4 (0, 80) -> (-4, 80)
  line L5 (-4, 80) -> (-4, 20)
  line L6 (-4, 20) -> (-65, 20)
  line L7 (-65, 20) -> (-65, 80)
  line L8 (-65, 80) -> (-69, 80)
  line L9 (-69, 80) -> (-69, 0)
  line L10 (-69, 0) -> (0, 0)
  line L11 (0, 0) -> (0, 80)
  line L12 (0, 0) -> (-20, 0)
  line L13 (-69, 0) -> (-49, 0)
  line L14 (-20, 0) -> (-49, 0) construction
  line L15 (-20, 0) -> (-23.5, 0) construction
  line L16 (-49, 0) -> (-45.5, 0) construction
  line L17 (-23.5, 0) -> (-45.5, 0) construction
  line L18 (-45.5, 0) -> (-45.5, -12.0344)
  line L19 (-45.5, -12.0344) -> (-23.5, -12.0344)
  line L20 (-23.5, -12.0344) -> (-23.5, 0)
  line L21 (-20, 0) -> (-49, 0) construction
  line L22 (-49, 0) -> (-49, -15)
  line L23 (-49, -15) -> (-20, -15)
  line L24 (-20, -15) -> (-20, 0)
  line L25 (-23.5, 0) -> (-23.5, -5) construction
  line L26 (-23.5, -5) -> (-21.5, -5)
  line L27 (-21.5, -5) -> (-21.5, -7)
  line L28 (-21.5, -7) -> (-23.5, -7)
  line L29 (-23.5, -7) -> (-23.5, -5) construction
  line L30 (-45.5, -5) -> (-47.5, -5)
  line L31 (-47.5, -5) -> (-47.5, -7)
  line L32 (-47.5, -7) -> (-45.5, -7)
  line L33 (-45.5, -7) -> (-45.5, -5)
  dimension "d32" = 20
  dimension "d33" = 20
  dimension "d34" = 3.5
  dimension "d35" = 3.5
  dimension "d36" = 2
  dimension "d37" = 2
  dimension "d38" = 2
  dimension "d39" = 2
  constraint coincident L10.end L11.start
  constraint perpendicular L11 L12
  constraint coincident L9.end L10.start
  constraint perpendicular L9 L13
  constraint parallel L14 L15
  constraint parallel L10 L16
  constraint horizontal L17
  constraint vertical L18
  constraint horizontal L19
  constraint vertical L20
  constraint horizontal L21
  constraint vertical L22
  constraint horizontal L23
  constraint vertical L24
  constraint coincident L20 L25.end
  constraint horizontal L26
  constraint vertical L27
  constraint horizontal L28
  constraint vertical L29
  constraint horizontal L30
  constraint vertical L31
  constraint horizontal L32
  constraint vertical L33
  constraint coincident L18 L30.start
  measures "d32" distance of L10.end L12.end
  measures "d33" distance of L9.end L13.end
  measures "d34" distance of L12.end L15.end
  measures "d35" distance of L13.end L16.end
  measures "d36" distance of L25.end L26.end
  measures "d37" distance of L25.end L28.end
  measures "d38" distance of L30.start L30.end
  measures "d39" distance of L30.start L32.end
extrude "拉伸7" add sketch "草图7" against normal blind 12 contours L10 L18 L19 L20 L22 L23 L24 L26 L27 L28 L30 L31 L32 bodies 1
sketch "草图8" plane through (0, 0, 15.7) normal (0, 0, 1) x (-1, 0, 0)
  line L0 (-45.476, -0.85) -> (-45.476, -11.35)
  arc A0 (-45.476, -11.35) -> (-44.726, -12.1) centre (-44.726, -11.35) ccw
  line L1 (-44.726, -12.1) -> (-23.926, -12.1)
  arc A1 (-23.926, -12.1) -> (-23.176, -11.35) centre (-23.926, -11.35) ccw
  line L2 (-23.176, -11.35) -> (-23.176, -0.85)
  arc A2 (-23.176, -0.85) -> (-23.926, -0.1) centre (-23.926, -0.85) ccw
  line L3 (-23.926, -0.1) -> (-44.726, -0.1)
  arc A3 (-44.726, -0.1) -> (-45.476, -0.85) centre (-44.726, -0.85) ccw
  line L4 (-30.376, -2.5) -> (-27.276, -2.5)
  line L5 (-27.276, -2.5) -> (-27.276, -3.6)
  line L6 (-27.276, -3.6) -> (-30.376, -3.6)
  line L7 (-30.376, -3.6) -> (-30.376, -2.5)
  line L8 (-34.576, -1.4115) -> (-34.576, -1.1)
  arc A4 (-34.576, -4.7) -> (-34.576, -1.1) centre (-35.0331, -2.9) ccw
  line L9 (-34.576, -4.7) -> (-34.576, -4.3885)
  arc A5 (-34.576, -4.3885) -> (-33.4838, -3.0557) centre (-35.0331, -2.9) ccw
  line L10 (-33.4838, -3.0557) -> (-34.576, -3.0557)
  line L11 (-34.576, -3.0557) -> (-34.576, -2.7443)
  line L12 (-34.576, -2.7443) -> (-33.4838, -2.7443)
  arc A6 (-33.4838, -2.7443) -> (-34.576, -1.4115) centre (-35.0331, -2.9) ccw
  line L13 (-33.076, -1.4115) -> (-33.076, -1.1)
  arc A7 (-33.076, -4.7) -> (-33.076, -1.1) centre (-33.5331, -2.9) ccw
  line L14 (-33.076, -4.7) -> (-33.076, -4.3885)
  arc A8 (-33.076, -4.3885) -> (-33.076, -1.4115) centre (-33.5331, -2.9) ccw
  circle A9 centre (-24.426, -10.45) radius 1
  circle A10 centre (-44.226, -10.45) radius 1
  circle A11 centre (-44.226, -1.75) radius 1
  circle A12 centre (-24.426, -1.75) radius 1
  line L15 (-39.9136, -9.3896) -> (-39.4227, -9.3896)
  line L16 (-39.4227, -9.3896) -> (-39.4227, -9.6)
  line L17 (-39.4227, -9.6) -> (-40.5915, -9.6)
  line L18 (-40.5915, -9.6) -> (-40.5915, -9.3896)
  line L19 (-40.5915, -9.3896) -> (-40.1006, -9.3896)
  line L20 (-40.1006, -9.3896) -> (-40.1006, -7.8)
  line L21 (-40.1006, -7.8) -> (-39.9136, -7.8)
  line L22 (-39.9136, -7.8) -> (-39.9136, -9.3896)
  line L23 (-40.8019, -9.6) -> (-41.3564, -9.6)
  spline S0 degree 3 poles (-41.3564, -9.6) (-41.3722, -9.6) (-41.4027, -9.6) (-41.4468, -9.5979) (-41.4877, -9.5957) (-41.5255, -9.5915) (-41.56, -9.5869) (-41.5912, -9.5812) (-41.6193, -9.5739) (-41.6367, -9.5681) (-41.645, -9.5653) knots 0 0 0 0 0.162643 0.312901 0.453294 0.58413 0.70285 0.811058 0.910586 1 1 1 1
  spline S1 degree 3 poles (-41.645, -9.5653) (-41.6554, -9.5613) (-41.6763, -9.5532) (-41.7057, -9.5372) (-41.7337, -9.5193) (-41.7601, -9.4988) (-41.7846, -9.4756) (-41.8077, -9.45) (-41.8289, -9.4217) (-41.8485, -9.3911) (-41.8666, -9.3586) (-41.8817, -9.3238) (-41.8951, -9.2875) (-41.9054, -9.2491) (-41.9141, -9.2091) (-41.9196, -9.1672) (-41.9235, -9.1234) (-41.9239, -9.0936) (-41.924, -9.0784) knots 0 0 0 0 0.056072 0.112012 0.167171 0.222811 0.27891 0.336355 0.395158 0.456072 0.518045 0.581404 0.645662 0.712108 0.780061 0.850885 0.92373 1 1 1 1
  spline S2 degree 3 poles (-41.924, -9.0784) (-41.9237, -9.0584) (-41.9231, -9.0193) (-41.9172, -8.9622) (-41.9073, -8.908) (-41.8938, -8.8565) (-41.8763, -8.8078) (-41.8547, -8.762) (-41.8293, -8.7189) (-41.8003, -8.6785) (-41.7661, -8.6418) (-41.7258, -8.6103) (-41.6802, -8.5834) (-41.6287, -8.5621) (-41.5718, -8.5448) (-41.5091, -8.533) (-41.4408, -8.5262) (-41.3934, -8.5252) (-41.3688, -8.5247) knots 0 0 0 0 0.066633 0.130318 0.191414 0.250222 0.307644 0.363778 0.418941 0.474177 0.529339 0.585724 0.64416 0.705484 0.771261 0.841987 0.917917 1 1 1 1
  line L24 (-41.3688, -8.5247) -> (-40.989, -8.5247)
  line L25 (-40.989, -8.5247) -> (-40.989, -7.8)
  line L26 (-40.989, -7.8) -> (-40.8019, -7.8)
  line L27 (-40.8019, -7.8) -> (-40.8019, -9.6)
  line L28 (-27.076, -4.2634) -> (-26.9704, -4.37)
  line L29 (-26.9704, -4.37) -> (-28.2172, -5.6048)
  line L30 (-28.2172, -5.6048) -> (-28.0549, -7.5525)
  line L31 (-28.0549, -7.5525) -> (-26.9704, -8.6265)
  line L32 (-26.9704, -8.6265) -> (-27.076, -8.7331)
  line L33 (-27.076, -8.7331) -> (-28.0358, -7.7826)
  line L34 (-28.0358, -7.7826) -> (-27.9885, -8.35)
  line L35 (-27.9885, -8.35) -> (-27.676, -8.35)
  line L36 (-27.676, -8.35) -> (-27.676, -8.5)
  line L37 (-27.676, -8.5) -> (-27.976, -8.5)
  arc A13 (-30.376, -8.5) -> (-27.976, -8.5) centre (-29.176, -7.6) ccw
  line L38 (-30.376, -8.5) -> (-30.376, -8)
  line L39 (-30.376, -8) -> (-30.6357, -8)
  line L40 (-30.6357, -8) -> (-31.376, -8.7331)
  line L41 (-31.376, -8.7331) -> (-31.4815, -8.6265)
  line L42 (-31.4815, -8.6265) -> (-30.776, -7.9278)
  line L43 (-30.776, -7.9278) -> (-30.776, -7.3)
  line L44 (-30.776, -7.3) -> (-30.376, -7.3)
  line L45 (-30.376, -7.3) -> (-30.376, -5.4649)
  line L46 (-30.376, -5.4649) -> (-31.4815, -4.37)
  line L47 (-31.4815, -4.37) -> (-31.376, -4.2634)
  line L48 (-31.376, -4.2634) -> (-30.5737, -5.0579)
  arc A14 (-29.8296, -4.9) -> (-30.5737, -5.0579) centre (-30.176, -5.1) ccw
  line L49 (-29.8296, -4.9) -> (-28.426, -4.9)
  line L50 (-28.426, -4.9) -> (-28.426, -4.6)
  line L51 (-28.426, -4.6) -> (-28.276, -4.6)
  line L52 (-28.276, -4.6) -> (-28.276, -4.9)
  line L53 (-28.276, -4.9) -> (-28.2335, -5.4098)
  line L54 (-28.2335, -5.4098) -> (-27.076, -4.2634)
  line L55 (-49.1786, -15) -> (-48.8574, -15) construction
  point P0 (-49.1786, -5.55)
extrude "拉伸8" add 1 faces at (20, 10, 8) along direction (-1, 0, 0) blind 2.5 on bodies 1 bodies 1
extrude "拉伸9" add 1 faces at (49, 5, 8) along direction (1, 0, 0) blind 2.5 on bodies 1 bodies 1
sketch "草图10" plane through (0, 0, -2.5) normal (0, 0, -1) x (1, 0, 0)
  arc A0 (49.1786, -5.55) -> (49.1786, -6.65) centre (48.226, -6.1) ccw
  line L0 (49.1786, -5.55) -> (50.376, -5.55)
  line L1 (50.376, -5.55) -> (50.376, -0.85)
  arc A1 (50.376, -0.85) -> (49.526, 0) centre (49.526, -0.85) ccw
  line L2 (49.526, 0) -> (44.726, 0)
  arc A2 (45.576, -0.85) -> (44.726, 0) centre (44.726, -0.85) ccw
  line L3 (45.576, -0.85) -> (45.576, -11.35)
  arc A3 (44.726, -12.2) -> (45.576, -11.35) centre (44.726, -11.35) ccw
  line L4 (44.726, -12.2) -> (49.526, -12.2)
  arc A4 (49.526, -12.2) -> (50.376, -11.35) centre (49.526, -11.35) ccw
  line L5 (50.376, -11.35) -> (50.376, -6.65)
  line L6 (50.376, -6.65) -> (49.1786, -6.65)
  circle A5 centre (48.226, -6.1) radius 1.1
  circle A6 centre (20.426, -6.1) radius 1.1
  arc A7 (19.4733, -6.65) -> (19.4733, -5.55) centre (20.426, -6.1) ccw
  dimension "d51" = 2.2
  constraint concentric A0 A5
  constraint concentric A6 A7
  measures "d51" diameter of A6
extrude "拉伸11" cut sketch "草图10" against normal blind 60 contours A0 A5 | A6 A7 bodies 1
sketch "草图11" plane through (0, 0, 12) normal (0, 0, 1) x (-1, 0, 0)
  arc A0 (-21.5, -6.3376) -> (-21.5, -5.8624) centre (-20.426, -6.1) ccw
  line L0 (-21.5, -6.3376) -> (-21.5, -7)
  line L1 (-21.5, -7) -> (-23.5, -7)
  line L2 (-23.5, -7) -> (-23.5, -12.0344)
  line L3 (-23.5, -12.0344) -> (-45.5, -12.0344)
  line L4 (-45.5, -12.0344) -> (-45.5, -7)
  line L5 (-45.5, -7) -> (-47.5, -7)
  line L6 (-47.5, -7) -> (-47.5, -6.9264)
  arc A1 (-47.5, -5.2736) -> (-47.5, -6.9264) centre (-48.226, -6.1) ccw
  line L7 (-47.5, -5.2736) -> (-47.5, -5)
  line L8 (-47.5, -5) -> (-45.5, -5)
  line L9 (-45.5, -5) -> (-45.5, 0)
  line L10 (-45.5, 0) -> (-23.5, 0)
  line L11 (-23.5, 0) -> (-23.5, -5)
  line L12 (-23.5, -5) -> (-21.5, -5)
  line L13 (-21.5, -5) -> (-21.5, -5.8624)
  line L14 (-17.5, 0) -> (0, 0)
  line L15 (0, 0) -> (0, 80)
  line L16 (0, 80) -> (-4, 80)
  line L17 (-4, 80) -> (-4, 20)
  line L18 (-4, 20) -> (-65, 20)
  line L19 (-65, 20) -> (-65, 80)
  line L20 (-65, 80) -> (-69, 80)
  line L21 (-69, 80) -> (-69, 0)
  line L22 (-69, 0) -> (-51.5, 0)
  line L23 (-51.5, 0) -> (-51.5, -15)
  line L24 (-51.5, -15) -> (-17.5, -15)
  line L25 (-17.5, -15) -> (-17.5, 0)
  line L26 (-65, 10) -> (-4, 10)
  line L27 (-4, 10) -> (-4, 5)
  line L28 (-4, 5) -> (-65, 5)
  line L29 (-65, 5) -> (-65, 10)
  line L30 (-23.167, -7) -> (-23.167, -5)
  line L31 (-47.5, -6.9264) -> (-45.576, -6.9264)
  line L32 (-45.576, -6.9264) -> (-45.576, -5)
  line L33 (-45.576, -5) -> (-47.5, -5)
  line L34 (-47.5, -5) -> (-47.5, -6.9264)
  line L35 (-21.5, -6.9402) -> (-23.0988, -6.9402)
  line L36 (-23.0988, -6.9402) -> (-23.0988, -7)
  line L37 (-23.0988, -7) -> (-21.5, -7)
  line L38 (-21.5, -7) -> (-21.5, -6.9402)
  constraint vertical L30
  constraint coincident L12 L30.end
  constraint horizontal L31
  constraint vertical L32
  constraint horizontal L33
  constraint vertical L34
  constraint coincident L8 L32.end
  constraint coincident L6.end A1.end
  constraint horizontal L35
  constraint vertical L36
  constraint horizontal L37
  constraint vertical L38
  constraint coincident L1 L36.end
  constraint coincident L0 L35.start
sketch "草图12" plane through (0, 0, 12) normal (0, 0, 1) x (-1, 0, 0)
  line L0 (-21.5, -7) -> (-23.167, -7)
  line L1 (-23.167, -7) -> (-23.167, -5)
  line L2 (-23.167, -5) -> (-21.5, -5)
  line L3 (-21.5, -5) -> (-21.5, -7)
  line L4 (-47.5, -5) -> (-45.5, -5)
  line L5 (-45.5, -5) -> (-45.5, -7)
  line L6 (-45.5, -7) -> (-47.5, -7)
  line L7 (-47.5, -7) -> (-47.5, -5)
  point P0 (-21.5, -7)
  point P1 (-23.167, -5)
  point P2 (-47.5, -5)
  point P3 (-45.5, -7)
  constraint horizontal L0
  constraint vertical L1
  constraint horizontal L2
  constraint vertical L3
  constraint coincident P1 L1.end
  constraint coincident P0 L0.start
  constraint horizontal L4
  constraint vertical L5
  constraint horizontal L6
  constraint vertical L7
  constraint coincident P3 L5.end
  constraint coincident P2 L4.start
extrude "拉伸12" add sketch "草图12" against normal blind 12 bodies 1
extrude "拉伸13" cut 1 faces at (23.5, 3.3333, 8) along direction (-1, 0, 0) blind 0.5 draft 5 on bodies 1 bodies 1
extrude "拉伸14" cut 1 faces at (23.5, 10.3563, 8) along direction (-1, 0, 0) blind 0.5 on bodies 1 bodies 1
extrude "拉伸15" cut 1 faces at (45.5, 8.0229, 4) along direction (1, 0, 0) blind 0.5 on bodies 1 bodies 1
extrude "拉伸16" cut 1 faces at (38.3333, 12.0344, 4) along direction (0, 1, 0) blind 1 on bodies 1 bodies 1
sketch "草图13" plane through (0, 0, 0) normal (0, 0, -1) x (1, 0, 0)
  line L0 (23, -13.0344) -> (23, -7)
  line L1 (23, -7) -> (23.167, -7)
  line L2 (23.167, -7) -> (23.167, -5.0291)
  line L3 (23.167, -5.0291) -> (23, -5.0437)
  line L4 (23, -5.0437) -> (23, 0.0437)
  line L5 (23, 0.0437) -> (23.5, 0)
  line L6 (23.5, 0) -> (46, 0)
  line L7 (46, 0) -> (46, -13.0344)
  line L8 (46, -13.0344) -> (23, -13.0344)
  arc A0 (21.5, -5.8624) -> (21.5, -6.3376) centre (20.426, -6.1) ccw
  line L9 (21.5, -5.8624) -> (21.5, -6.3376)
  line L10 (17.5, -15) -> (51.5, -15)
  line L11 (51.5, -15) -> (51.5, 0)
  line L12 (51.5, 0) -> (69, 0)
  line L13 (69, 0) -> (69, 80)
  line L14 (69, 80) -> (65, 80)
  line L15 (65, 80) -> (65, 20)
  line L16 (65, 20) -> (4, 20)
  line L17 (4, 20) -> (4, 80)
  line L18 (4, 80) -> (0, 80)
  line L19 (0, 80) -> (0, 0)
  line L20 (0, 0) -> (17.5, 0)
  line L21 (17.5, 0) -> (17.5, -15)
  line L22 (4, 10) -> (65, 10)
  line L23 (65, 10) -> (65, 5)
  line L24 (65, 5) -> (4, 5)
  line L25 (4, 5) -> (4, 10)
  line L26 (47.5, -6.9264) -> (47.5, -5.2736)
  arc A1 (47.5, -6.9264) -> (47.5, -5.2736) centre (48.226, -6.1) ccw
  circle A2 centre (48.226, -6.1) radius 1.1
  line L27 (23.167, -7) -> (23, -7)
  line L28 (23, -7) -> (23, -5.0437)
  line L29 (23, -5.0437) -> (23.167, -5.0437)
  line L30 (23.167, -5.0437) -> (23.167, -7)
  dimension "d64" = 2.2
  constraint concentric A1 A2
  constraint horizontal L27
  constraint vertical L28
  constraint horizontal L29
  constraint vertical L30
  constraint coincident L3.end L4.start
  constraint coincident L1.end L2.start
  measures "d64" diameter of A2
extrude "拉伸17" cut sketch "草图13" against normal blind 60 contours L1 L2 L27 L28 L29 L30 | L26 A2 bodies 1
sketch "草图14" plane through (0, 0, 0) normal (0, 0, -1) x (1, 0, 0)
  circle A0 centre (48.226, -6.1) radius 1.1
  line L0 (4, 10) -> (65, 10)
  line L1 (65, 10) -> (65, 5)
  line L2 (65, 5) -> (4, 5)
  line L3 (4, 5) -> (4, 10)
  line L4 (17.5, -15) -> (51.5, -15)
  line L5 (51.5, -15) -> (51.5, 0)
  line L6 (51.5, 0) -> (69, 0)
  line L7 (69, 0) -> (69, 80)
  line L8 (69, 80) -> (65, 80)
  line L9 (65, 80) -> (65, 20)
  line L10 (65, 20) -> (4, 20)
  line L11 (4, 20) -> (4, 80)
  line L12 (4, 80) -> (0, 80)
  line L13 (0, 80) -> (0, 0)
  line L14 (0, 0) -> (17.5, 0)
  line L15 (17.5, 0) -> (17.5, -15)
  arc A1 (21.5, -5.8624) -> (21.5, -6.3376) centre (20.426, -6.1) ccw
  line L16 (21.5, -5.8624) -> (21.5, -6.3376)
  line L17 (23, -13.0344) -> (23, -5.0437)
  line L18 (23, -5.0437) -> (23, 0.0437)
  line L19 (23, 0.0437) -> (23.5, 0)
  line L20 (23.5, 0) -> (46, 0)
  line L21 (46, 0) -> (46, -13.0344)
  line L22 (46, -13.0344) -> (23, -13.0344)
  line L23 (51.5, 0) -> (61, 0)
  dimension "d67" = 9.5
  constraint coincident L5.end L6.start
  constraint perpendicular L5 L23
  measures "d67" distance of L5.end L23.end
sketch "草图15" plane through (0, 0, 12) normal (0, 0, 1) x (-1, 0, 0)
  line L0 (-51.5, 0) -> (-51.5, -15) construction
  line L1 (-51.5, 0) -> (-61, 0) construction
  line L2 (-61, 0) -> (-66, 0) construction
  line L3 (-61, 0) -> (-66, 0)
  line L4 (-66, 0) -> (-66, -40)
  line L5 (-66, -40) -> (-61, -40)
  line L6 (-61, -40) -> (-61, 0)
  point P0 (-51.5, 0)
  point P1 (-61, 0)
  dimension "d68" = 5
  dimension "d69" = 40
  constraint coincident P0 L0.start
  constraint coincident P1 L1.end
  constraint parallel L1 L2
  constraint horizontal L3
  constraint vertical L4
  constraint horizontal L5
  constraint vertical L6
  measures "d68" distance of P1 L2.end
  measures "d69" distance of P1 L5.end
extrude "拉伸18" add sketch "草图15" against normal blind 29 separate body makes body 2
extrude "拉伸19" add 1 faces at (64.3333, 13.3333, -17) along direction (0, 0, -1) blind 12 on bodies 2 bodies 2
sketch "草图16" plane through (0, 0, 12) normal (0, 0, 1) x (-1, 0, 0)
  line L0 (-17.5, -15) -> (-51.5, -15)
  line L1 (-51.5, -15) -> (-51.5, 0)
  line L2 (-51.5, 0) -> (-17.5, 0)
  line L3 (-17.5, 0) -> (-17.5, -15)
  point P0 (-17.5, -15)
  point P1 (-51.5, 0)
  constraint horizontal L0
  constraint vertical L1
  constraint horizontal L2
  constraint vertical L3
  constraint coincident P1 L1.end
  constraint coincident P0 L0.start
extrude "拉伸20" cut sketch "草图16" against normal blind 2 bodies 1

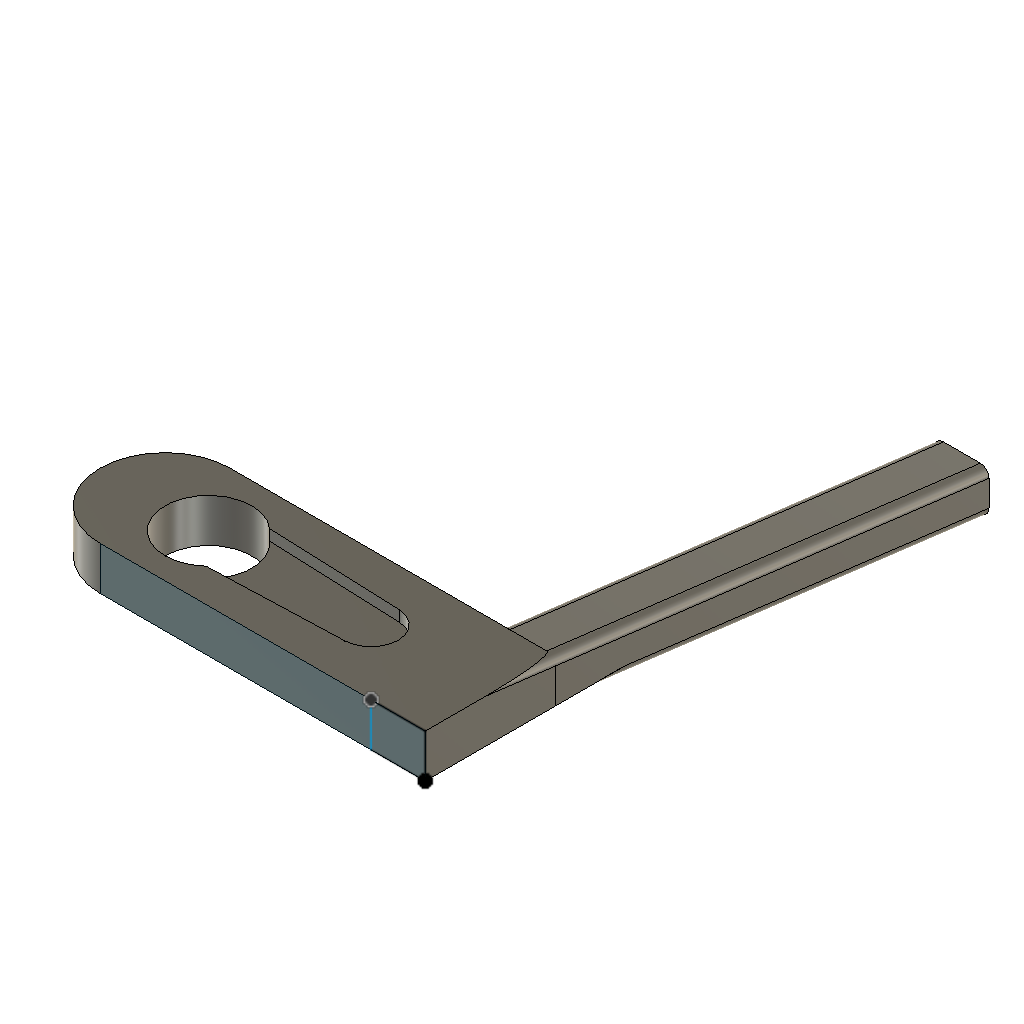
design "τê¬µ¥å"
part number: 2026-10-11-11-10-36-620
Autodesk Fusion 360 part; units mm, degrees
sketch "草图22" plane through (0, 0, 0) normal (0, 0, 1) x (1, 0, 0)
  line L0 (120, 0) -> (145, 0) construction
  line L1 (120, 0) -> (145, 0)
  line L2 (145, 0) -> (145, -12)
  line L3 (145, -12) -> (120, -12)
  line L4 (120, -12) -> (120, 0)
  circle A0 centre (120, -6) radius 6
  line L5 (120, -6) -> (124, -6) construction
  line L6 (124, -6) -> (128, -6) construction
  line L7 (124, -6) -> (139, -6) construction
  line L8 (124, -6) -> (126.646, -6) construction
  circle A1 centre (124, -6) radius 4
  dimension "d89" = 25
  dimension "d90" = 12
  dimension "d91" = 4
  dimension "d92" = 4
  dimension "d93" = 15
  dimension "d94" = 2.646
  dimension "d95" = 8
  constraint horizontal L0
  constraint horizontal L1
  constraint vertical L2
  constraint horizontal L3
  constraint vertical L4
  constraint coincident L0.start A0
  constraint coincident L3.end A0
  constraint tangent L3 A0
  constraint coincident A0.centre L5.start
  constraint perpendicular L4 L5
  constraint parallel L5 L6
  constraint parallel L6 L7
  constraint parallel L7 L8
  constraint coincident L5.end L6.start
  measures "d89" distance of L0.start L0.end
  measures "d90" distance of L0.start L3.end
  measures "d91" distance of A0.centre L5.end
  measures "d92" distance of L5.end L6.end
  measures "d93" distance of L5.end L7.end
  measures "d94" distance of L5.end L8.end
  measures "d95" diameter of A1
extrude "拉伸18" add sketch "草图22" along normal blind 4 contours L4 A0 A1 | L4 A0 | L1 L2 L3 A0 A1 | L4 A0 A1
sketch "草图23" plane through (0, 0, 4) normal (0, 0, 1) x (-1, 0, 0)
  circle A0 centre (-124, 6) radius 4
  arc A1 (-120, 0) -> (-120, 12) centre (-120, 6) ccw
  line L0 (-120, 12) -> (-145, 12)
  line L1 (-145, 12) -> (-145, 0)
  line L2 (-145, 0) -> (-120, 0)
  line L3 (-124, 6) -> (-126.646, 6)
  line L4 (-124, 6) -> (-139, 6) construction
  circle A2 centre (-139, 6) radius 2.5
  line L5 (-126.6574, 3.0103) -> (-139.0987, 3.5019)
  line L6 (-126.714, 8.9384) -> (-139.0888, 8.4984)
  dimension "d98" = 2.646
  dimension "d99" = 15
  dimension "d100" = 5
  constraint coincident A0.centre L3.start
  constraint horizontal L3
  constraint parallel L3 L4
  constraint coincident L4.end A2.centre
  constraint coincident A0 L5.start
  constraint coincident A2 L5.end
  constraint tangent A2 L5
  constraint coincident A0 L6.start
  constraint coincident A2 L6.end
  constraint tangent A2 L6
  measures "d98" distance of A0.centre L3.end
  measures "d99" distance of A0.centre L4.end
  measures "d100" diameter of A2
extrude "拉伸19" cut sketch "草图23" against normal blind 1 contours A0 A2 L5 L6 | A2
extrude "拉伸20" add 1 faces at (145, -4, 1.3333) along direction (1, 0, 0) blind 5
sketch "草图24" plane through (0, -12, 0) normal (0, -1, 0) x (1, 0, 0)
  line L0 (120, 0) -> (150, 0)
  line L1 (150, 0) -> (150, 4)
  line L2 (150, 4) -> (120, 4)
  line L3 (120, 4) -> (120, 0)
  line L4 (150, 0) -> (145, 0)
  line L5 (145, 0) -> (145, 4)
  line L6 (145, 4) -> (150, 4)
  line L7 (150, 4) -> (150, 0)
  constraint horizontal L4
  constraint vertical L5
  constraint horizontal L6
  constraint vertical L7
  constraint coincident L2 L5.end
  constraint coincident L0.end L1.start
sketch "草图25" plane through (0, 0, 0) normal (0, 1, 0) x (-1, 0, 0)
  line L0 (-150, 0) -> (-120, 0)
  line L1 (-120, 0) -> (-120, 4)
  line L2 (-120, 4) -> (-150, 4)
  line L3 (-150, 4) -> (-150, 0)
  line L4 (-150, 0) -> (-145, 0)
  line L5 (-145, 0) -> (-145, 4)
  line L6 (-145, 4) -> (-150, 4)
  line L7 (-150, 4) -> (-150, 0)
  point P0 (-145, 4)
  constraint horizontal L4
  constraint vertical L5
  constraint horizontal L6
  constraint vertical L7
  constraint coincident P0 L5.end
  constraint coincident L0.start L3.end
ref_plane "工作平面1" through (147.5, 40, 2) normal (0, 1, 0) x (-1, 0, 0)
sketch "草图26" plane through (0, 40, 0) normal (0, 1, 0) x (1, 0, 0)
  line L0 (150, 5) -> (145, 5)
  line L1 (145, 5) -> (145, 1)
  line L2 (145, 1) -> (150, 1)
  line L3 (150, 1) -> (150, 5)
  constraint horizontal L0
  constraint vertical L1
  constraint horizontal L2
  constraint vertical L3
loft "放样1" add profiles "草图25", "草图26" section 1 contours L0 L2 L3 L4 L5 L6 L7 section 2
fillet "圆角1" radius 0.8 4 edges at (145, 20, -2.5) (145, 20, 1.5) (150, 20, 1.5) (150, 20, -2.5)
